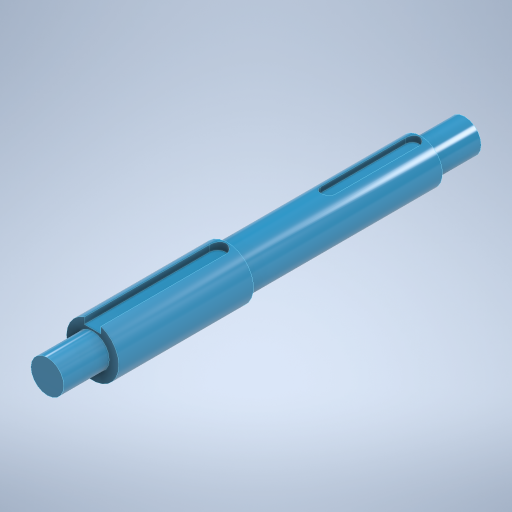
# Autodesk Inventor part: Layshaft
Saved by Autodesk Inventor 2023 (Build 270158000, 158)
## iProperties
Created: 2024-05-11
Part Number: Layshaft
Material: Generic
Document SubType Name: Modeling
Designer: BenFr
Density: 1 g/cm^3
Appearance: Sky Blue Dark
Author: BenFr
Autodesk Inventor part; units mm, degrees
ref_plane "YZ Plane" through (0, 0, 0) normal (1, 0, 0) x (0, 1, 0)
ref_plane "XZ Plane" through (0, 0, 0) normal (0, 1, 0) x (-1, 0, 0)
sketch "Sketch1" plane through (0, 0, 0) normal (0, 1, 0) x (-1, 0, 0)
  line L0 (0, 0) -> (0, -151.85)
  line L1 (0, 0) -> (6, 0)
  line L2 (6, 0) -> (6, -16.5)
  line L3 (6, -16.5) -> (9.525, -16.5)
  line L4 (9.525, -16.5) -> (9.525, -65.5)
  line L5 (0, -151.85) -> (6, -151.85)
  line L6 (6, -151.85) -> (6, -135.85)
  line L7 (6, -135.85) -> (7.9375, -135.85)
  line L8 (7.9375, -135.85) -> (7.9375, -65.5)
  line L9 (7.9375, -65.5) -> (9.525, -65.5)
  dimension "d0" = 151.85
  dimension "d1" = 6
  dimension "d2" = 16.5
  dimension "d3" = 3.525
  dimension "d4" = 49
  dimension "d5" = 6
  dimension "d6" = 16
  dimension "d7" = 1.9375
  constraints: 20 end point, 5 perpendicular, 3 horizontal, 2 vertical
  measures "d0" distance of L0.start L0.end
  measures "d1" distance of L0.start L1.end
  measures "d2" distance of L1.end L2.end
  measures "d3" distance of L2.end L3.end
  measures "d4" distance of L3.end L4.end
  measures "d5" distance of L0.end L5.end
  measures "d6" distance of L5.end L6.end
  measures "d7" distance of L6.end L7.end
revolve "Revolution1" add sketch "Sketch1" angle 360 about axis through (0, 0, 0) along (0, 0, -1)
sketch "Sketch2" plane through (0, 0, -16.5) normal (0, 0, 1) x (1, 0, 0)
  line L0 (-3, 6.675) -> (3, 6.675)
  line L1 (3, 6.675) -> (3, 12.375)
  line L2 (3, 12.375) -> (-3, 12.375)
  line L3 (-3, 12.375) -> (-3, 6.675)
  circle A0 centre (0, 0) radius 9.525 projected
  line L4 (-3, 6.675) -> (3, 12.375) construction
  line L5 (3, 6.675) -> (-3, 12.375) construction
  point P0 (0, 9.525)
  dimension "d9" = 6
  dimension "d10" = 5.7
  constraints: 12 end point, 2 midpoint, 2 parallel, 1 horizontal, 1 perpendicular, 1 vertical alignment, 1 other
  measures "d9" distance of L2.end L1.end
  measures "d10" distance of L1.end L0.end
extrude "Extrusion1" cut sketch "Sketch2" against normal blind 48.5 contours L3 A0 L1 L0 | L3 L2 L1 A0 picked at (-0.3385, 7.6069)
fillet "Fillet1" radius 3 2 edges at (-3, 7.8576, -65) (3, 7.8576, -65)
ref_plane "Work Plane1" through (0, 0, -135.35) normal (0, 0, -1) x (-1, 0, 0)
sketch "Sketch4" plane through (0, 0, -135.35) normal (0, 0, -1) x (-1, 0, 0)
  line L0 (-2.5, 5.5875) -> (2.5, 5.5875)
  line L1 (2.5, 5.5875) -> (2.5, 10.2875)
  line L2 (2.5, 10.2875) -> (-2.5, 10.2875)
  line L3 (-2.5, 10.2875) -> (-2.5, 5.5875)
  circle A0 centre (0, 0) radius 7.9375 projected
  line L4 (-2.5, 5.5875) -> (2.5, 10.2875) construction
  line L5 (2.5, 5.5875) -> (-2.5, 10.2875) construction
  point P0 (0, 7.9375)
  dimension "d17" = 5
  dimension "d18" = 4.7
  constraints: 12 end point, 2 midpoint, 2 parallel, 1 horizontal, 1 perpendicular, 1 vertical alignment, 1 other
  measures "d17" distance of L2.end L1.end
  measures "d18" distance of L1.end L0.end
extrude "Extrusion2" cut sketch "Sketch4" against normal blind 35.8 contours L3 A0 L1 L0 | L3 L2 L1 A0 picked at (-0.2821, 6.3558)
fillet "Fillet2" radius 2.5 4 edges at (-2.5, 6.5605, -99.55) (2.5, 6.5605, -99.55) (2.5, 6.5605, -135.35) (-2.5, 6.5605, -135.35)
body "Solid1"
